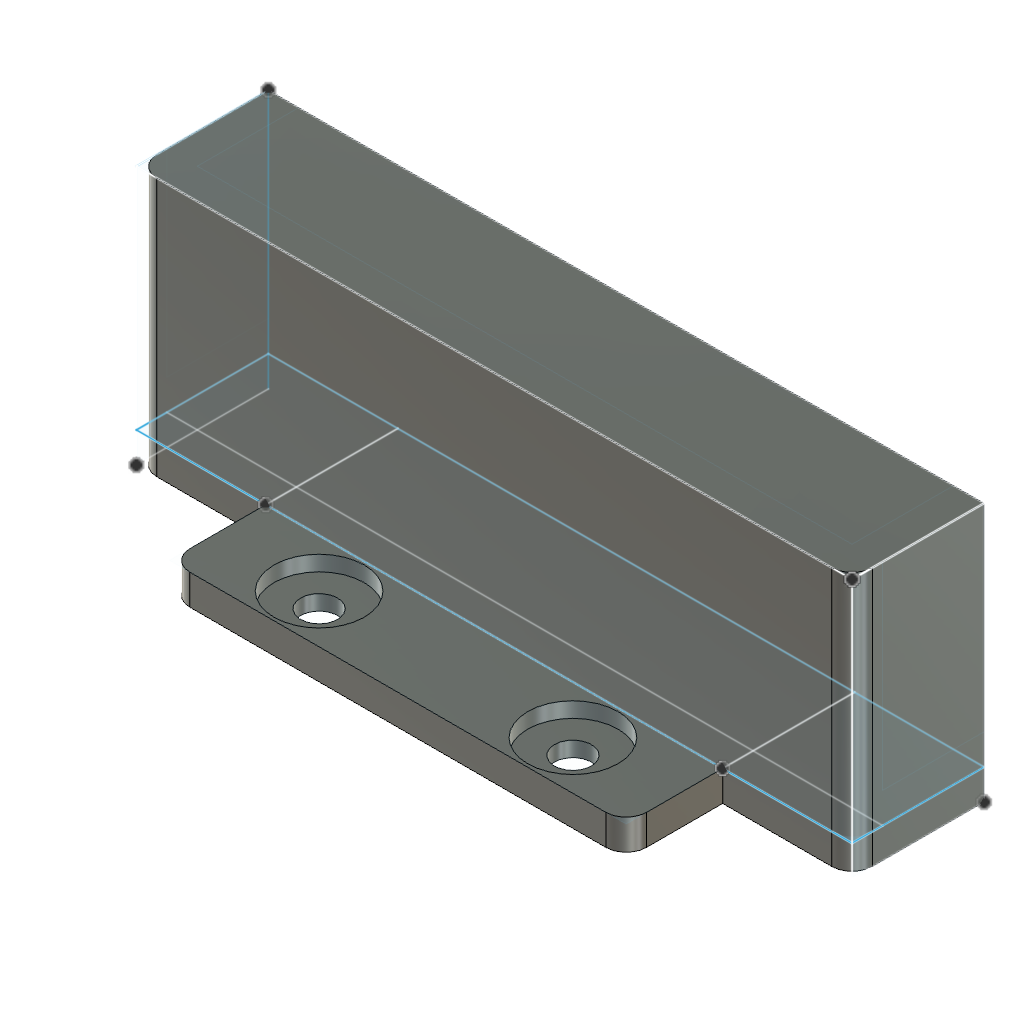
PowerBoardTop (Autodesk Fusion 360 design; units mm, degrees)
part number: 2026-08-10-19-56-16-923
Autodesk Fusion 360 part; units mm, degrees
sketch "Sketch1" plane through (0, 0, 0) normal (0, 0, 1) x (1, 0, 0)
  line L0 (-28, 37) -> (62, 37)
  line L1 (62, 37) -> (62, 18)
  line L2 (62, 18) -> (-28, 18)
  line L3 (-28, 18) -> (-28, 37)
  dimension "d1" = 90
  dimension "d2" = 19
  constraint horizontal L0
  constraint vertical L1
  constraint horizontal L2
  constraint vertical L3
  measures "d1" distance of L0.start L0.end
  measures "d2" distance of L0.start L2.end
extrude "Extrude1" add sketch "Sketch1" along normal blind 6 makes body 1
sketch "Sketch2" plane through (0, 0, 6) normal (0, 0, 1) x (-1, 0, 0)
  line L0 (28, -37) -> (28, -18)
  line L1 (28, -18) -> (-62, -18)
  line L2 (-62, -18) -> (-62, -37)
  line L3 (-62, -37) -> (28, -37)
ref_plane "WorkPlane1" through (17, 27.5, 6) normal (0, 0, 1) x (-1, 0, 0)
sketch "Sketch3" plane through (0, 0, 6) normal (0, 0, 1) x (1, 0, 0)
  line L0 (17, 37) -> (17, 18)
  circle A0 centre (-8, 27.5) radius 8.9
  circle A1 centre (42, 27.5) radius 8.9
  circle A2 centre (-8, 27.5) radius 3.65
  circle A3 centre (42, 27.5) radius 3.65
  dimension "d13" = 17.8
  dimension "d14" = 17.8
  dimension "d15" = 7.3
  dimension "d16" = 7.3
  constraint vertical L0
  constraint concentric A0 A2
  constraint concentric A1 A3
  measures "d13" diameter of A0
  measures "d14" diameter of A1
  measures "d15" diameter of A2
  measures "d16" diameter of A3
extrude "Extrude2" cut sketch "Sketch3" against normal blind 7 contours A2 | A3 bodies 1
extrude "Extrude3" cut sketch "Sketch3" against normal blind 3 bodies 1
sketch "Sketch7" plane through (0, 0, 6) normal (0, 0, 1) x (-1, 0, 0)
  circle A0 centre (-42, -27.5) radius 8.9
  circle A1 centre (8, -27.5) radius 8.9
  line L0 (28, -18) -> (-62, -18)
  line L1 (-62, -18) -> (-62, -37)
  line L2 (-62, -37) -> (28, -37)
  line L3 (28, -37) -> (28, -18)
  line L4 (-62, -37) -> (-87.5, -37)
  line L5 (-87.5, -37) -> (-87.5, -63)
  line L6 (-87.5, -63) -> (-62, -63)
  line L7 (-62, -63) -> (-62, -37)
  line L8 (28, -37) -> (53.5, -37)
  line L9 (53.5, -37) -> (53.5, -63)
  line L10 (53.5, -63) -> (28, -63)
  line L11 (28, -63) -> (28, -37)
  line L12 (-62, -37) -> (28, -37)
  line L13 (28, -37) -> (28, -63)
  line L14 (28, -63) -> (-62, -63)
  line L15 (-62, -63) -> (-62, -37)
  line L16 (-87.5, -37) -> (53.5, -37)
  line L17 (53.5, -37) -> (53.5, -43)
  line L18 (53.5, -43) -> (-87.5, -43)
  line L19 (-87.5, -43) -> (-87.5, -37)
  dimension "d37" = 25.5
  dimension "d38" = 26
  dimension "d39" = 25.5
  dimension "d40" = 26
  dimension "d41" = 6
  constraint horizontal L4
  constraint vertical L5
  constraint horizontal L6
  constraint vertical L7
  constraint coincident L1.end L2.start
  constraint horizontal L8
  constraint vertical L9
  constraint horizontal L10
  constraint vertical L11
  constraint coincident L2.end L3.start
  constraint horizontal L12
  constraint vertical L13
  constraint horizontal L14
  constraint vertical L15
  constraint horizontal L16
  constraint vertical L17
  constraint horizontal L18
  constraint vertical L19
  measures "d37" distance of L1.end L4.end
  measures "d38" distance of L1.end L6.end
  measures "d39" distance of L2.end L8.end
  measures "d40" distance of L2.end L10.end
  measures "d41" distance of L4.end L18.end
extrude "Extrude7" add sketch "Sketch7" along normal blind 45 separate body contours L2 L7 L11 L12 L13 L15 L16 L18 | L8 L9 L11 L13 L16 L17 L18 | L4 L5 L7 L15 L16 L18 L19 makes body 2
extrude "Extrude8" add sketch "Sketch7" along normal blind 6 contours L9 L10 L11 L13 L18 | L7 L11 L13 L14 L15 L18 | L5 L6 L7 L15 L18 bodies 2
sketch "Sketch8" plane through (0, 0, 6) normal (0, 0, 1) x (-1, 0, 0)
  line L0 (53.5, -37) -> (-87.4788, -37)
  line L1 (-87.4788, -37) -> (-87.4788, -62.9728)
  line L2 (-87.4788, -62.9728) -> (53.5, -62.9728)
  line L3 (53.5, -62.9728) -> (53.5, -37)
  constraint horizontal L0
  constraint vertical L1
  constraint horizontal L2
  constraint vertical L3
extrude "Extrude9" add sketch "Sketch7" sketch "Sketch8" against normal blind 6 contours L2 L7 L11 L12 L13 L15 L16 L18 | L4 L5 L7 L15 L16 L18 L19 | L9 L10 L11 L13 L18 | L7 L11 L13 L14 L15 L18 | L5 L6 L7 L15 L18 of sketch 2 bodies 1 2
sketch "Sketch9" plane through (87.5, 0, 0) normal (1, 0, 0) x (0, 1, 0)
  line L0 (63, 0) -> (63, 12)
  line L1 (63, 12) -> (43, 12)
  line L2 (43, 12) -> (43, 51)
  line L3 (43, 51) -> (37, 51)
  line L4 (37, 51) -> (37, 0)
  line L5 (37, 0) -> (63, 0)
  line L6 (37, 51) -> (63, 51)
  line L7 (63, 51) -> (63, 0)
  line L8 (63, 0) -> (37, 0)
  line L9 (37, 0) -> (37, 51)
  constraint horizontal L6
  constraint vertical L7
  constraint horizontal L8
  constraint vertical L9
  constraint coincident L0.start L5.end
  constraint coincident L3.end L4.start
extrude "Extrude10" add sketch "Sketch9" against normal blind 6 contours L1 L2 L6 L7 bodies 1
sketch "Sketch10" plane through (-53.5, 0, 0) normal (-1, 0, 0) x (0, -1, 0)
  line L0 (-37, 0) -> (-37, 51)
  line L1 (-37, 51) -> (-43, 51)
  line L2 (-43, 51) -> (-43, 12)
  line L3 (-43, 12) -> (-63, 12)
  line L4 (-63, 12) -> (-63, 0)
  line L5 (-63, 0) -> (-37, 0)
  line L6 (-63, 51) -> (-37, 51)
  line L7 (-37, 51) -> (-37, 0)
  line L8 (-37, 0) -> (-63, 0)
  line L9 (-63, 0) -> (-63, 51)
  constraint horizontal L6
  constraint vertical L7
  constraint horizontal L8
  constraint vertical L9
  constraint coincident L0.start L5.end
extrude "Extrude11" add sketch "Sketch10" against normal blind 6 contours L2 L3 L6 L9 bodies 1
sketch "Sketch11" plane through (0, 0, 51) normal (0, 0, 1) x (-1, 0, 0)
  line L0 (-81.5, -43) -> (47.5, -43)
  line L1 (47.5, -43) -> (47.5, -63)
  line L2 (47.5, -63) -> (53.5, -63)
  line L3 (53.5, -63) -> (53.5, -37)
  line L4 (53.5, -37) -> (-87.5, -37)
  line L5 (-87.5, -37) -> (-87.5, -63)
  line L6 (-87.5, -63) -> (-81.5, -63)
  line L7 (-81.5, -63) -> (-81.5, -43)
  line L8 (-87.5, -37) -> (53.5, -37)
  line L9 (53.5, -37) -> (53.5, -63)
  line L10 (53.5, -63) -> (-87.5, -63)
  line L11 (-87.5, -63) -> (-87.5, -37)
  constraint horizontal L8
  constraint vertical L9
  constraint horizontal L10
  constraint vertical L11
  constraint coincident L2.end L3.start
  constraint coincident L4.end L5.start
extrude "Extrude12" add sketch "Sketch11" against normal blind 6 contours L0 L1 L7 L10 bodies 1
fillet "Fillet3" radius 4 1 edges at (-53.5, 37, 25.5) on bodies 1
fillet "Fillet4" radius 4 1 edges at (-28, 18, 3) on bodies 1
fillet "Fillet5" radius 4 1 edges at (62, 18, 3) on bodies 1
fillet "Fillet6" radius 4 1 edges at (87.5, 37, 25.5) on bodies 1
